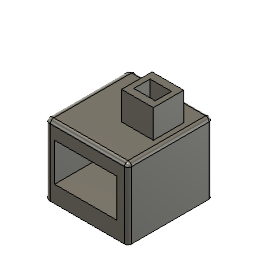
dp2 (Autodesk Fusion 360 design; units mm, degrees)
part number: 2026-08-20-13-49-05-923
part number: 2026-08-20-13-49-42-939
Autodesk Fusion 360 part; units mm, degrees
sketch "Sketch1" plane through (0, 0, 0) normal (0, 1, 0) x (1, 0, 0) in component "MAIN BODY"
  line L0 (30, -19.764) -> (-270, -19.764)
  line L1 (-270, -19.764) -> (-270, 280.236)
  line L2 (-270, 280.236) -> (30, 280.236)
  line L3 (30, 280.236) -> (30, -19.764)
  dimension "d1" = 300
  dimension "d2" = 300
  constraint horizontal L0
  constraint vertical L1
  constraint horizontal L2
  constraint vertical L3
  measures "d1" distance of L0.start L0.end
  measures "d2" distance of L0.end L1.end
extrude "Extrude1" add sketch "Sketch1" along normal blind 250 makes body 1 in component "MAIN BODY"
sketch "Sketch2" plane through (0, 0, 19.764) normal (0, 0, 1) x (1, 0, 0) in component "MAIN BODY"
  line L0 (-270, 0) -> (30, 0)
  line L1 (30, 0) -> (30, 250)
  line L2 (30, 250) -> (-270, 250)
  line L3 (-270, 250) -> (-270, 0)
  line L4 (-230, 60) -> (-10, 60)
  line L5 (-10, 60) -> (-10, 195.1449)
  line L6 (-10, 195.1449) -> (-230, 195.1449)
  line L7 (-230, 195.1449) -> (-230, 60)
  dimension "d5" = 220
  dimension "d6" = 40
  dimension "d7" = 60
  constraint horizontal L4
  constraint vertical L5
  constraint horizontal L6
  constraint vertical L7
  measures "d5" distance of L5.end L6.end
  measures "d6" distance of L3 L7
  measures "d7" distance of L0 L4
extrude "Extrude2" cut sketch "Sketch2" against normal blind 290 contours L4 L5 L6 L7 bodies 1 in component "MAIN BODY"
sketch "Sketch3" plane through (0, 250, 0) normal (0, 1, 0) x (-1, 0, 0) in component "MAIN BODY"
  line L0 (-30, -280.236) -> (270, -280.236)
  line L1 (270, -280.236) -> (270, 19.764)
  line L2 (270, 19.764) -> (-30, 19.764)
  line L3 (-30, 19.764) -> (-30, -280.236)
  line L4 (112.363, -207.8082) -> (0, -207.8082)
  line L5 (0, -207.8082) -> (0, -100)
  line L6 (0, -100) -> (112.363, -100)
  line L7 (112.363, -100) -> (112.363, -207.8082)
  constraint horizontal L4
  constraint vertical L5
  constraint horizontal L6
  constraint vertical L7
extrude "Extrude3" cut sketch "Sketch3" against normal blind 60 contours L4 L5 L6 L7 bodies 1 in component "MAIN BODY"
move_face "MoveFace1" by (50, 0, 0) 1 faces at (-156.6667, 150.0966, -270.236) on bodies 1 in component "MAIN BODY"
move_face "MoveFace2" by (30, 0, 0) 1 faces at (-156.6667, 150.0966, -270.236) on bodies 1 in component "MAIN BODY"
move_face "MoveFace3" by (0, 70, 0) 1 faces at (-156.6667, 150.0966, -270.236) on bodies 1 in component "MAIN BODY"
move_face "MoveFace4" by (0, 30, 0) 1 faces at (-156.6667, 150.0966, -270.236) on bodies 1 in component "MAIN BODY"
fillet "Fillet1" radius 12.5 1 edges at (-120, 250, 19.764) on bodies 1 in component "MAIN BODY"
fillet "Fillet2" radius 12.5 1 edges at (-120, 250, -280.236) on bodies 1 in component "MAIN BODY"
fillet "Fillet3" radius 12.5 5 edges at (30, 118.75, 19.764) (30, 246.3388, 16.1029) (30, 250, -130.236) (30, 246.3388, -276.5748) (30, 118.75, -280.236) on bodies 1 in component "MAIN BODY"
fillet "Fillet4" radius 25 5 edges at (-270, 118.75, -280.236) (-270, 246.3388, -276.5748) (-270, 250, -130.236) (-270, 246.3388, 16.1029) (-270, 118.75, 19.764) on bodies 1 in component "MAIN BODY"
sketch "Sketch4" plane through (0, 250, 0) normal (0, 1, 0) x (-1, 0, 0) in component "MAIN BODY"
  line L0 (245, -267.736) -> (245, 7.264)
  line L1 (245, 7.264) -> (-17.5, 7.264)
  line L2 (-17.5, 7.264) -> (-17.5, -267.736)
  line L3 (-17.5, -267.736) -> (245, -267.736)
  line L4 (0, -207.8082) -> (0, -100)
  line L5 (0, -100) -> (112.363, -100)
  line L6 (112.363, -100) -> (112.363, -207.8082)
  line L7 (112.363, -207.8082) -> (0, -207.8082)
extrude "Extrude4" add sketch "Sketch4" along normal blind 50 separate body contours L4 L5 L6 L7 makes body 2 in component "MAIN BODY"
extrude "Extrude5" add 1 faces at (-37.4543, 300, -135.9361) along direction (0, 1, 0) blind 25 on bodies 2 bodies 2 in component "MAIN BODY"
extrude "Extrude6" add 1 faces at (-37.4543, 325, -135.9361) along direction (0, 1, 0) blind 25 on bodies 2 bodies 2 in component "MAIN BODY"
sketch "Sketch5" plane through (0, 350, 0) normal (0, 1, 0) x (-1, 0, 0) in component "MAIN BODY"
  line L0 (112.363, -207.8082) -> (112.363, -100)
  line L1 (112.363, -100) -> (0, -100)
  line L2 (0, -100) -> (0, -207.8082)
  line L3 (0, -207.8082) -> (112.363, -207.8082)
  line L4 (93.5619, -181.9669) -> (17.681, -181.9669)
  line L5 (17.681, -181.9669) -> (17.681, -124.5037)
  line L6 (17.681, -124.5037) -> (93.5619, -124.5037)
  line L7 (93.5619, -124.5037) -> (93.5619, -181.9669)
  constraint horizontal L4
  constraint vertical L5
  constraint horizontal L6
  constraint vertical L7
extrude "Extrude7" cut sketch "Sketch5" against normal blind 150 contours L4 L5 L6 L7 bodies 2 in component "MAIN BODY"
ref_plane "WorkPlane1" through (-56.1815, 375, -153.9041) normal (0, 1, 0) x (0, 0, 1) in component "MAIN BODY"
sketch "Sketch6" plane through (0, 375, 0) normal (0, 1, 0) x (1, 0, 0) in component "MAIN BODY"
ref_plane "WorkPlane2" through (-56.1815, 425, -153.9041) normal (0, 1, 0) x (0, 0, 1) in component "MAIN BODY"
component "MAIN BODY" placed x (1, 0, 0) y (0, 1, 0) z (0, 0, 1) at (0, 0, 0)
